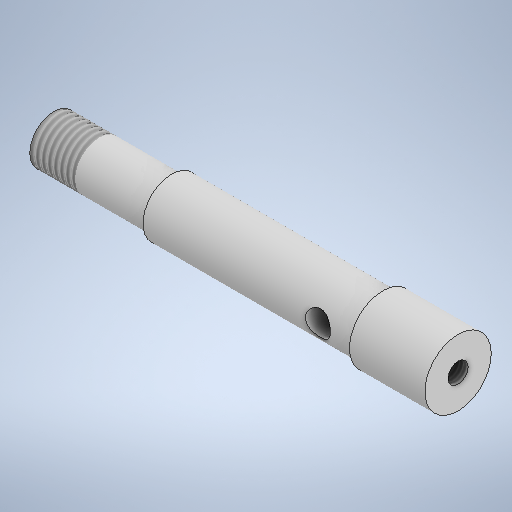
# Autodesk Inventor part: Eje de acero
Saved by Autodesk Inventor 2025.3 (Build 293356030, 356C)
## iProperties
Created: 2025-08-17
Part Number: Eje de acero
Material: Generic
Document SubType Name: Modeling
Designer: PC
Density: 1 g/cm^3
Appearance: Default
Author: PC
Autodesk Inventor part; units mm, degrees
ref_plane "YZ Plane" through (0, 0, 0) normal (1, 0, 0) x (0, 1, 0)
ref_plane "XZ Plane" through (0, 0, 0) normal (0, 1, 0) x (-1, 0, 0)
sketch "Sketch1" plane through (0, 0, 0) normal (0, 1, 0) x (-1, 0, 0)
  line L0 (0, 0) -> (67, 0)
  line L1 (0, 0) -> (-67, 0)
  line L2 (-67, 0) -> (-67, -11)
  line L3 (-67, -11) -> (-42, -11)
  line L4 (-42, -11) -> (-42, -9.5)
  line L5 (-42, -9.5) -> (28, -9.5)
  line L6 (28, -9.5) -> (28, -8)
  line L7 (28, -8) -> (67, -8)
  line L8 (67, -8) -> (67, 0)
  circle A0 centre (39, -9.5875) radius 9.525
  point P0 (48.3918, -8)
  point P1 (29.6082, -8)
  dimension "d0" = 67
  dimension "d1" = 67
  dimension "d2" = 11
  dimension "d3" = 25
  dimension "d4" = 9.5
  dimension "d5" = 8
  dimension "d6" = 70
  dimension "d7" = 19.05
  dimension "d8" = 1.5875
  dimension "d9" = 11
  constraints: 18 end point, 3 perpendicular, 3 vertical, 2 horizontal, 1 centre point, 1 parallel
  measures "d0" distance of L0.start L0.end
  measures "d1" distance of L0.start L1.end
  measures "d2" distance of L1.end L2.end
  measures "d3" distance of L2.end L3.end
  measures "d4" distance between parallel lines of L0 L5
  measures "d5" distance between parallel lines of L0 L7
  measures "d6" distance of L4.end L5.end
  measures "d7" diameter of A0
  measures "d8" distance from line of L7 A0.centre
  measures "d9" distance from line of L6 A0.centre
revolve "Revolution1" add sketch "Sketch1" angle 360 about axis through (0, 0, 0) along (-1, 0, 0) picked at (38.2641, -5.4406) contours L0 L8 L7 A0 L6 L5 L4 L3 L2 L1 | L7 A0
extrude "Extrusion1" cut sketch "Sketch1" along normal mid plane 3.175 contours L7 A0 picked at (38.2641, -5.4406)
thread "Thread1" size "M16x2" class "6g" standard "ANSI Metric M Profile" length 15 offset 24
sketch "Sketch2" plane through (67, 0, 0) normal (1, 0, 0) x (0, 0, -1)
  circle A0 centre (0, 0) radius 11 projected
  constraints: 1 coincident
hole "Hole1" at (67, 0, 0) direction (-1, 0, 0) diameter 6.647 depth 44 tip angle 118 thread size "M8x1.25" class "6H" standard "ISO Metric profile"
ref_plane "Work Plane1" through (7, 0, -9.5) normal (0, 0, 1) x (1, 0, 0)
sketch "Sketch3" plane through (7, 0, -9.5) normal (0, 0, 1) x (1, 0, 0)
  line L0 (35, 11) -> (35, -11) projected
  point P0 (-7, 0)
  point P1 (23, 0)
  dimension "d22" = 12
  measures "d22" distance from line of point (23, 0) L0
hole "Hole2" at (30, 0, -9.5) direction (0, 0, 1) diameter 8.3 end through all
body "Solid1"
